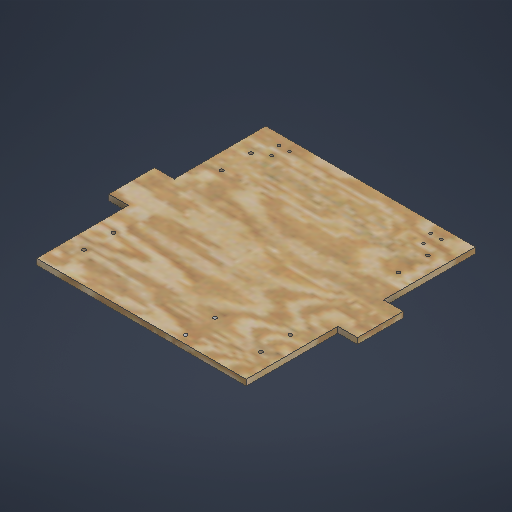
# Autodesk Inventor part: plateau_grand_robot_bas
Saved by Autodesk Inventor 2026 (Build 300175000, 175)
## iProperties
Created: 2025-05-12
Part Number: plateau_grand_robot_bas
Material: Generisch
Document SubType Name: Modeling
Designer: karle
Density: 1 g/cm^3
Appearance: Vorgabe
Author: karle
Autodesk Inventor part; units mm, degrees
ref_plane "YZ Plane" through (0, 0, 0) normal (1, 0, 0) x (0, 1, 0)
ref_plane "XZ Plane" through (0, 0, 0) normal (0, 1, 0) x (-1, 0, 0)
ref_plane "XY Plane" through (0, 0, 0) normal (0, 0, 1) x (1, 0, 0)
sketch "Skizze1" plane through (0, 0, 0) normal (0, 0, 1) x (1, 0, 0)
  line L0 (-190, 175) -> (190, 175)
  line L1 (190, 175) -> (190, -175)
  line L2 (190, -175) -> (-190, -175)
  line L3 (-190, -175) -> (-190, 175)
  point P0 (0, 0)
  point P1 (190, 0)
  dimension "d0" = 350
  dimension "d1" = 380
  dimension "d2" = 190
  dimension "d3" = 175
  constraints: 8 end point, 2 parallel, 1 horizontal, 1 midpoint, 1 perpendicular
  measures "d0" distance of L0.end L1.end
  measures "d1" distance of L1.end L2.end
  measures "d2" distance of point (190, 0) point (0, 0)
  measures "d3" distance from line of point (0, 0) L0
extrude "Extrusion1" add sketch "Skizze1" against normal blind 9
sketch "Skizze2" plane through (0, 0, 0) normal (0, 0, 1) x (1, 0, 0)
  line L0 (190, -175) -> (190, 175) projected
  line L1 (-190, 175) -> (-190, -175) projected
  line L2 (-190, -175) -> (190, -175) projected
  line L3 (190, 175) -> (-190, 175) projected
  line L4 (-108, 159) -> (-124, 159) construction
  line L5 (0, 226.773) -> (0, -251.9389) construction
  line L6 (108, 159) -> (124, 159) construction
  point P0 (0, 0)
  point P1 (-116, 140)
  point P2 (116, 140)
  dimension "d21" = 19
  dimension "d22" = 16
  dimension "d23" = 8
  dimension "d24" = 66
  dimension "d25" = 16
  constraints: 6 end point, 3 symmetric about line, 1 horizontal, 1 vertical
  measures "d21" distance from line of point (-116, 140) L4
  measures "d22" distance of L4.end L4.start
  measures "d23" horizontal distance of L4.start point (-116, 140)
  measures "d24" distance from line of L1 L4.end
  measures "d25" distance from line of L3 L4.end
hole "Bohrung1" at (-108, 159, 0) at (-124, 159, 0) at (-116, 140, 0) at (124, 159, 0) at (116, 140, 0) at (108, 159, 0) direction (0, 0, -1) diameter 4.3 end through all
sketch "Sketch3" plane through (0, 0, 0) normal (0, 0, 1) x (1, 0, 0)
  line L0 (0, 217.718) -> (0, -359.0364) construction
  line L1 (-190, 175) -> (-190, -175) projected
  line L2 (190, 175) -> (-190, 175) projected
  line L3 (-135, 127.5) -> (-135, 82.5) construction
  line L4 (-315.7106, 0) -> (348.4737, 0) construction
  line L5 (-135, -127.5) -> (-135, -82.5) construction
  line L6 (135, 127.5) -> (135, 82.5) construction
  line L7 (135, -127.5) -> (135, -82.5) construction
  line L8 (55, -117.5) -> (55, -162.5) construction
  line L9 (190, -175) -> (190, 175) construction
  line L10 (-190, -175) -> (190, -175) construction
  point P0 (0, 0)
  dimension "d26" = 45
  dimension "d27" = 55
  dimension "d28" = 47.5
  dimension "d43" = 135
  dimension "d44" = 45
  dimension "d45" = 12.5
  constraints: 14 end point, 6 symmetric about line, 3 vertical, 2 coincident, 1 horizontal
  measures "d26" distance of L3.end L3.start
  measures "d27" distance from line of L1 L3.start
  measures "d28" distance from line of L2 L3.start
  measures "d43" distance between parallel lines of L9 L8
  measures "d44" distance of L8.start L8.end
  measures "d45" distance from line of L10 point (55, -162.5)
hole "Hole2" at (-135, -127.5, 0) at (-135, -82.5, 0) at (135, 127.5, 0) at (135, 82.5, 0) at (135, -127.5, 0) at (135, -82.5, 0) at (-135, 127.5, 0) at (-135, 82.5, 0) at (55, -162.5, 0) at (55, -117.5, 0) direction (0, 0, -1) diameter 5.5 end through all
sketch "Sketch4" plane through (0, 0, 0) normal (0, 0, 1) x (1, 0, 0)
  line L0 (-190, -175) -> (-160, -175)
  line L1 (-160, -175) -> (-160, -35)
  line L2 (-160, -35) -> (-190, -35)
  line L3 (-190, -35) -> (-190, -175)
  line L4 (-205.9459, 0) -> (216.1424, 0) construction
  line L5 (0, 231.698) -> (0, -262.7483) construction
  line L6 (190, -175) -> (160, -175)
  line L7 (160, -175) -> (160, -35)
  line L8 (160, -35) -> (190, -35)
  line L9 (190, -35) -> (190, -175)
  line L10 (-190, 175) -> (-160, 175)
  line L11 (-160, 175) -> (-160, 35)
  line L12 (-160, 35) -> (-190, 35)
  line L13 (-190, 35) -> (-190, 175)
  line L14 (190, 175) -> (160, 175)
  line L15 (160, 175) -> (160, 35)
  line L16 (160, 35) -> (190, 35)
  line L17 (190, 35) -> (190, 175)
  point P0 (0, 0)
  dimension "d36" = 140
  dimension "d37" = 30
  constraints: 36 end point, 15 symmetric about line, 4 coincident, 2 horizontal, 2 parallel, 1 perpendicular, 1 vertical
  measures "d36" distance of L2.end L0.start
  measures "d37" distance of L0.start L0.end
extrude "Extrusion2" cut sketch "Sketch4" against normal blind 10
